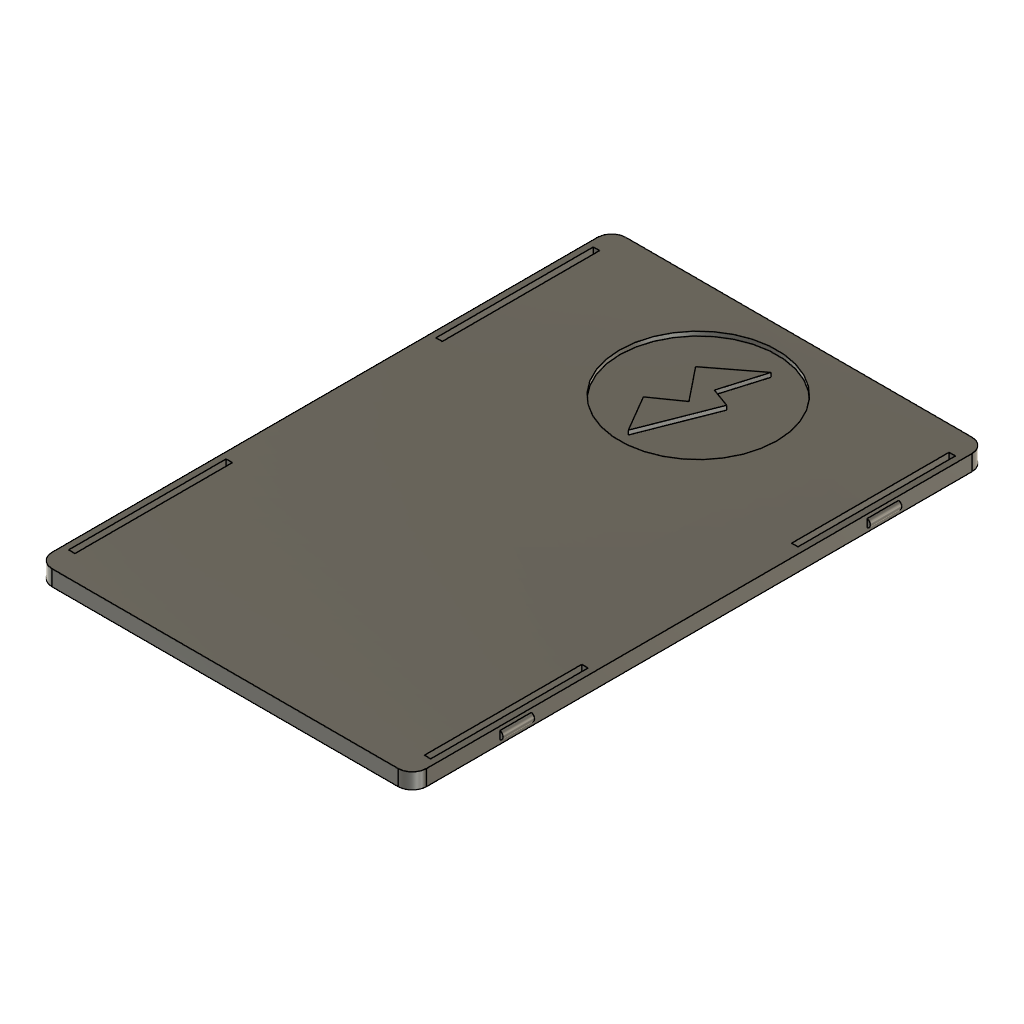
Hatch (Autodesk Fusion 360 design; units mm, degrees)
part number: 2026-10-19-10-28-42-767
Autodesk Fusion 360 part; units mm, degrees
sketch "Sketch1" plane through (0, 0, 0) normal (0, 0, 1) x (1, 0, 0)
  line L0 (-47, 95.3) -> (19, 95.3)
  arc A0 (19, 95.3) -> (21.7, 98) centre (19, 98) ccw
  line L1 (21.7, 98) -> (21.7, 202)
  arc A1 (21.7, 202) -> (19, 204.7) centre (19, 202) ccw
  line L2 (19, 204.7) -> (-47, 204.7)
  arc A2 (-47, 204.7) -> (-49.7, 202) centre (-47, 202) ccw
  line L3 (-49.7, 202) -> (-49.7, 98)
  arc A3 (-49.7, 98) -> (-47, 95.3) centre (-47, 98) ccw
extrude "hatch_plate" add sketch "Sketch1" along normal blind 3 from surface at 80
sketch "hatch_flex_slot" plane through (0, 0, 0) normal (0, 0, 1) x (1, 0, 0)
  line L0 (-48.5, 100) -> (-47.3, 100)
  line L1 (-47.3, 100) -> (-47.3, 130)
  line L2 (-47.3, 130) -> (-48.5, 130)
  line L3 (-48.5, 130) -> (-48.5, 100)
extrude "hatch_flex_slot (1)" cut sketch "hatch_flex_slot" along normal blind 4 from surface at 79.5
sketch "hatch_bump" plane through (0, 0, 0) normal (0, 1, 0) x (1, 0, 0)
  circle A0 centre (-49.5, -81.5) radius 0.8
extrude "hatch_bump (1)" add sketch "hatch_bump" along normal blind 6 from surface at 112
sketch "hatch_flex_slot (1)" plane through (0, 0, 0) normal (0, 0, 1) x (1, 0, 0)
  line L0 (-48.5, 170) -> (-47.3, 170)
  line L1 (-47.3, 170) -> (-47.3, 200)
  line L2 (-47.3, 200) -> (-48.5, 200)
  line L3 (-48.5, 200) -> (-48.5, 170)
extrude "hatch_flex_slot (2)" cut sketch "hatch_flex_slot (1)" along normal blind 4 from surface at 79.5
sketch "hatch_bump (1)" plane through (0, 0, 0) normal (0, 1, 0) x (1, 0, 0)
  circle A0 centre (-49.5, -81.5) radius 0.8
extrude "hatch_bump (2)" add sketch "hatch_bump (1)" along normal blind 6 from surface at 182
sketch "hatch_flex_slot (2)" plane through (0, 0, 0) normal (0, 0, 1) x (1, 0, 0)
  line L0 (19.3, 100) -> (20.5, 100)
  line L1 (20.5, 100) -> (20.5, 130)
  line L2 (20.5, 130) -> (19.3, 130)
  line L3 (19.3, 130) -> (19.3, 100)
extrude "hatch_flex_slot (3)" cut sketch "hatch_flex_slot (2)" along normal blind 4 from surface at 79.5
sketch "hatch_bump (2)" plane through (0, 0, 0) normal (0, 1, 0) x (1, 0, 0)
  circle A0 centre (21.5, -81.5) radius 0.8
extrude "hatch_bump (3)" add sketch "hatch_bump (2)" along normal blind 6 from surface at 112
sketch "hatch_flex_slot (3)" plane through (0, 0, 0) normal (0, 0, 1) x (1, 0, 0)
  line L0 (19.3, 170) -> (20.5, 170)
  line L1 (20.5, 170) -> (20.5, 200)
  line L2 (20.5, 200) -> (19.3, 200)
  line L3 (19.3, 200) -> (19.3, 170)
extrude "hatch_flex_slot (4)" cut sketch "hatch_flex_slot (3)" along normal blind 4 from surface at 79.5
sketch "hatch_bump (3)" plane through (0, 0, 0) normal (0, 1, 0) x (1, 0, 0)
  circle A0 centre (21.5, -81.5) radius 0.8
extrude "hatch_bump (4)" add sketch "hatch_bump (3)" along normal blind 6 from surface at 182
sketch "surge_mark" plane through (0, 0, 0) normal (0, 0, 1) x (1, 0, 0)
  circle A0 centre (-14, 185.5) radius 15
  line L0 (-9.6624, 186.5727) -> (-14.9225, 173.1004)
  line L1 (-14.9225, 173.1004) -> (-18.9815, 180.0201)
  line L2 (-18.9815, 180.0201) -> (-13.8747, 183.6048)
  line L3 (-13.8747, 183.6048) -> (-16.4314, 186.7952)
  line L4 (-16.4314, 186.7952) -> (-18.9878, 189.9857)
  line L5 (-18.9878, 189.9857) -> (-10.8541, 196.2216)
  line L6 (-10.8541, 196.2216) -> (-13.329, 187.9154)
  line L7 (-13.329, 187.9154) -> (-9.6624, 186.5727)
extrude "surge_mark (1)" cut sketch "surge_mark" against normal blind 1.3 from surface at 83.5
equation "d1042 = -( 1.30 mm )"
named bodies: "Hatch"
